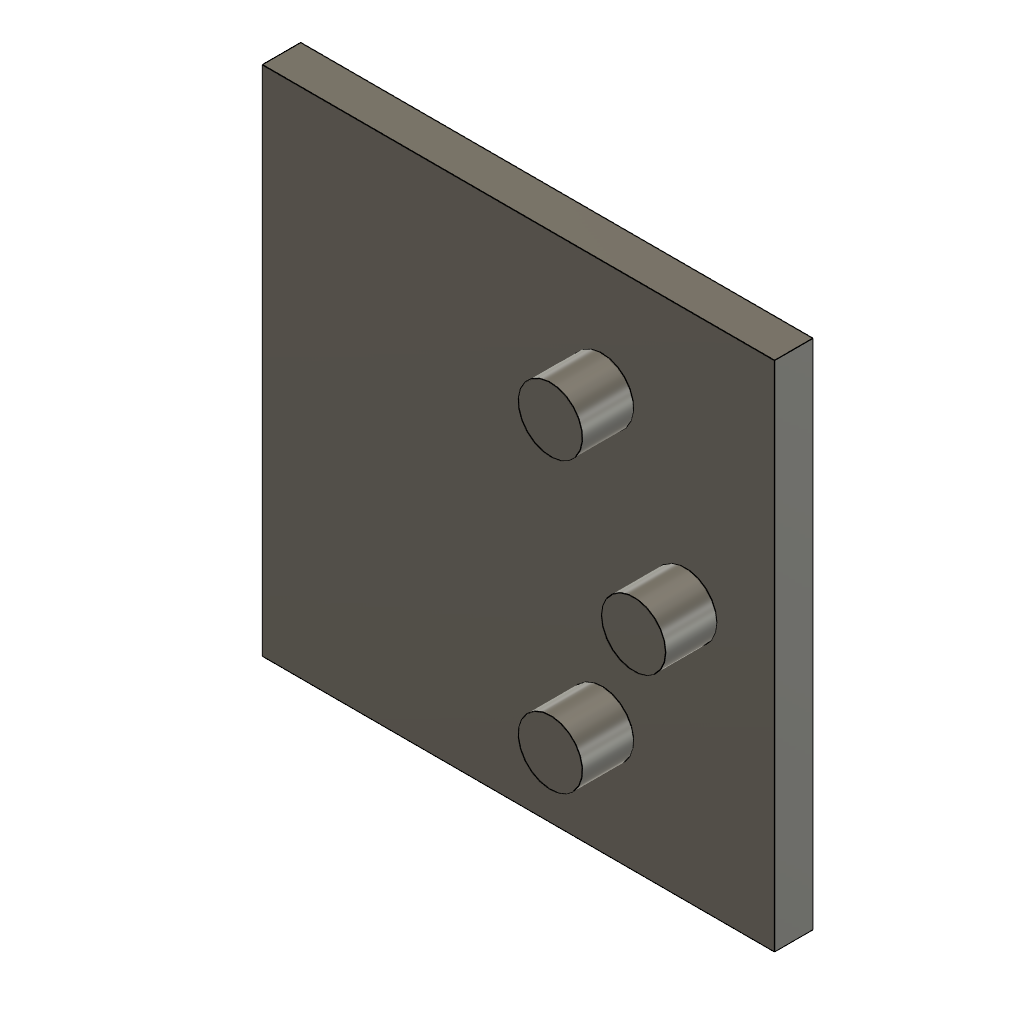
pat_circ_symmetric (Autodesk Fusion 360 design; units mm, degrees)
part number: 2026-11-13-14-45-30-856
Autodesk Fusion 360 part; units mm, degrees
sketch "Sketch1" plane through (0, 0, 0) normal (0, 0, 1) x (1, 0, 0)
  line L0 (-20, -20) -> (20, -20)
  line L1 (20, -20) -> (20, 20)
  line L2 (20, 20) -> (-20, 20)
  line L3 (-20, 20) -> (-20, -20)
extrude "Extrude1" add sketch "Sketch1" along normal blind 3
sketch "Sketch2" plane through (0, 0, 3) normal (0, 0, 1) x (1, 0, 0)
  line L0 (-20, 20) -> (-20, -20)
  line L1 (-20, -20) -> (20, -20)
  line L2 (20, -20) -> (20, 20)
  line L3 (20, 20) -> (-20, 20)
  circle A0 centre (13, 0) radius 2.5
extrude "Extrude2" add sketch "Sketch2" along normal blind 4 contours A0
pattern_circular "C-Pattern1" count 3 over 120 about axis through (0, 0, 1.75) along (0, 0, 1) both ways of "Extrude2"
